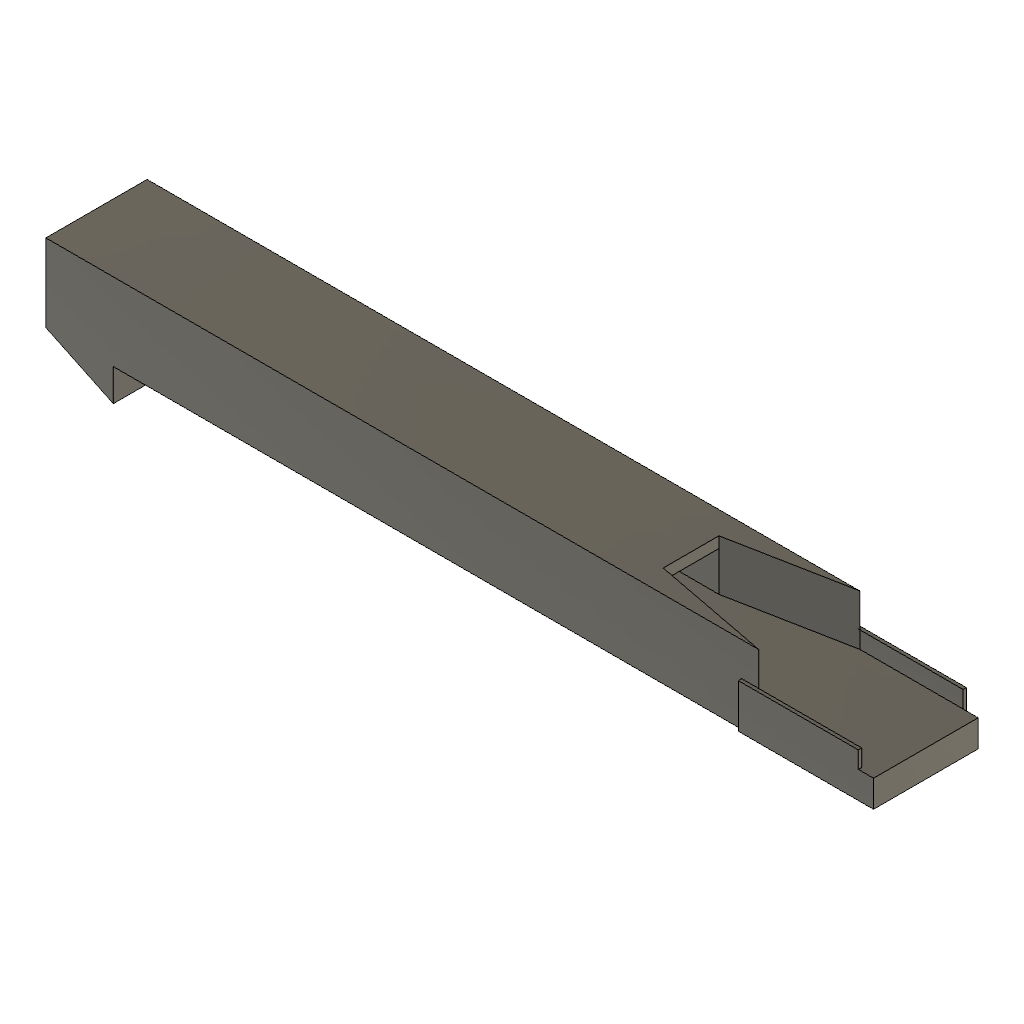
Lego ramp center (Autodesk Fusion 360 design; units mm, degrees)
Autodesk Fusion 360 part; units mm, degrees
sketch "Sketch1" plane through (0, 0, 0) normal (0, 0, 1) x (1, 0, 0)
  line L0 (-79, 15) -> (79, 15)
  line L1 (79, 15) -> (79, -15)
  line L2 (79, -15) -> (-79, -15)
  line L3 (-79, -15) -> (-79, 15)
  line L4 (-79, 15) -> (79, -15) construction
  line L5 (79, 15) -> (-79, -15) construction
  line L6 (79, 8.25) -> (-79, 8.25)
  line L7 (-79, 8.25) -> (-79, -8.25)
  line L8 (-79, -8.25) -> (79, -8.25)
  line L9 (79, -8.25) -> (79, 8.25)
  line L10 (79, 8.25) -> (-79, -8.25) construction
  line L11 (-79, 8.25) -> (79, -8.25) construction
  dimension "d1" = 158
  dimension "d2" = 30
  dimension "d3" = 16.5
  constraint horizontal L0
  constraint perpendicular L0 L1
  constraint parallel L0 L2
  constraint parallel L1 L3
  constraint coincident L4 origin
  constraint coincident L5 origin
  constraint horizontal L6
  constraint perpendicular L6 L7
  constraint parallel L6 L8
  constraint parallel L7 L9
  constraint coincident L10 origin
  constraint coincident L11 origin
  constraint coincident L3 L7.end
  measures "d1" distance of L1.end L2.end
  measures "d2" distance of L0.end L1.end
  measures "d3" distance of L6.end L7.end
extrude "Extrude1" add sketch "Sketch1" against normal blind 5 makes body 1
sketch "Sketch2" plane through (0, 0, 0) normal (0, 0, 1) x (-1, 0, 0)
  line L0 (-79, 15) -> (-79, -15)
  line L1 (-79, -15) -> (79, -15)
  line L2 (79, -15) -> (79, 15)
  line L3 (79, 15) -> (-79, 15)
  line L4 (-79, -8.25) -> (79, -8.25)
  line L5 (79, -8.25) -> (79, 8.25)
  line L6 (79, 8.25) -> (-79, 8.25)
  line L7 (-79, 8.25) -> (-79, -8.25)
  line L8 (-79, -8.25) -> (79, 8.25) construction
  line L9 (79, -8.25) -> (-79, 8.25) construction
  point P0 (-79, -8.25)
  constraint horizontal L4
  constraint perpendicular L4 L5
  constraint parallel L4 L6
  constraint parallel L5 L7
  constraint coincident L8 origin
  constraint coincident L9 origin
  constraint coincident P0 L4.start
extrude "Extrude10" add sketch "Sketch2" along normal blind 15 contours L0 L2 L3 L6 | L0 L1 L2 L4 bodies 1
sketch "Sketch3" plane through (0, 0, 0) normal (0, 0, 1) x (-1, 0, 0)
  line L0 (-79, 8.25) -> (-79, -8.25)
  line L1 (79, -8.25) -> (79, 8.25)
  line L2 (-67, -8.25) -> (-50, -8.25)
  line L3 (-50, -8.25) -> (-50, 8.25)
  line L4 (-50, 8.25) -> (-67, 8.25)
  line L5 (-67, 8.25) -> (-67, -8.25)
  line L6 (-67, -8.25) -> (-50, 8.25) construction
  line L7 (-50, -8.25) -> (-67, 8.25) construction
  line L8 (-18, -8.25) -> (7, -8.25)
  line L9 (7, -8.25) -> (7, 8.25)
  line L10 (7, 8.25) -> (-18, 8.25)
  line L11 (-18, 8.25) -> (-18, -8.25)
  line L12 (-18, -8.25) -> (7, 8.25) construction
  line L13 (7, -8.25) -> (-18, 8.25) construction
  line L14 (32, -8.25) -> (65, -8.25)
  line L15 (65, -8.25) -> (65, 8.25)
  line L16 (65, 8.25) -> (32, 8.25)
  line L17 (32, 8.25) -> (32, -8.25)
  line L18 (32, -8.25) -> (65, 8.25) construction
  line L19 (65, -8.25) -> (32, 8.25) construction
  line L20 (-79, -8.25) -> (79, -8.25)
  line L21 (79, 8.25) -> (-79, 8.25)
  point P0 (-58.5, 0)
  point P1 (-5.5, 0)
  point P2 (48.5, 0)
  dimension "d60" = 17
  dimension "d61" = 16.5
  dimension "d64" = 25
  dimension "d65" = 16.5
  dimension "d67" = 33
  dimension "d68" = 16.5
  dimension "d94" = 25
  dimension "d95" = 32
  dimension "d128" = 12
  constraint horizontal L2
  constraint perpendicular L2 L3
  constraint parallel L2 L4
  constraint parallel L3 L5
  constraint coincident L6 P0
  constraint coincident L7 P0
  constraint horizontal L8
  constraint perpendicular L8 L9
  constraint parallel L8 L10
  constraint parallel L9 L11
  constraint coincident L12 P1
  constraint coincident L13 P1
  constraint horizontal L14
  constraint perpendicular L14 L15
  constraint parallel L14 L16
  constraint parallel L15 L17
  constraint coincident L18 P2
  constraint coincident L19 P2
  measures "d60" distance of L3.end L4.end
  measures "d61" distance of L2.end L3.end
  measures "d64" distance of L9.end L10.end
  measures "d65" distance of L8.end L9.end
  measures "d67" distance of L15.end L16.end
  measures "d68" distance of L14.end L15.end
  measures "d94" distance of L9 L17
  measures "d95" distance of L3 L11
  measures "d128" distance of L0 L5
sketch "Sketch5" plane through (79, 0, 0) normal (1, 0, 0) x (0, 1, 0)
  line L0 (-15, 15) -> (-15, -5)
  line L1 (-15, -5) -> (15, -5)
  line L2 (8.25, 0) -> (8.25, 15)
  line L3 (-8.25, 10) -> (8.25, 10)
  line L4 (-1.0004, 11.75) -> (-7, 11.75)
  line L5 (-7, 11.75) -> (-7, 9.9815)
  line L6 (-1.0004, 9.9102) -> (-1.0004, 11.75)
  line L7 (-1.0004, 11.75) -> (-7, 9.9815) construction
  line L8 (-7, 11.75) -> (-1.0004, 9.9102) construction
  line L9 (7, 11.75) -> (1, 11.75)
  line L10 (1, 11.75) -> (1, 10)
  line L11 (1, 10) -> (7, 10)
  line L12 (7, 10) -> (7, 11.75)
  line L13 (7, 11.75) -> (1, 10) construction
  line L14 (1, 11.75) -> (7, 10) construction
  line L15 (1, 10.5) -> (-1.0004, 10.5)
  line L16 (7, 10.25) -> (8.25, 10.25)
  line L17 (-7, 10.25) -> (-8.25, 10.25)
  line L18 (8.25, 0) -> (-8.25, 0)
  line L19 (15, -5) -> (15, 15)
  line L20 (-8.25, 0) -> (-8.25, 15)
  line L21 (-8.25, 15) -> (-15, 15)
  line L22 (15, 15) -> (8.25, 15)
  line L23 (8.25, 15) -> (8.25, 0)
  line L24 (-8.25, 15) -> (8.25, 15)
  point P0 (-4.0595, 10.8483)
  point P1 (4, 10.875)
  dimension "d36" = 6
  dimension "d45" = 1.75
  dimension "d48" = 6
  dimension "d49" = 1.75
  dimension "d54" = 1.75
  dimension "d55" = 0.5
  dimension "d56" = 0.25
  dimension "d57" = 0.25
  constraint coincident L2.start L18.start
  constraint horizontal L4
  constraint perpendicular L4 L5
  constraint parallel L5 L6
  constraint coincident L7 P0
  constraint coincident L8 P0
  constraint horizontal L9
  constraint perpendicular L9 L10
  constraint parallel L9 L11
  constraint parallel L10 L12
  constraint coincident L13 P1
  constraint coincident L14 P1
  constraint coincident L10 L15.start
  constraint coincident L6 L15.end
  constraint perpendicular L6 L15
  constraint coincident L12 L16.start
  constraint coincident L5 L17.start
  constraint coincident L20.end L21.start
  constraint coincident L2.end L22.end
  measures "d36" distance of L5.end L6.start
  measures "d45" distance of L3 L4
  measures "d48" distance of L10.end L11.end
  measures "d49" distance of L9.end L10.end
  measures "d54" distance of L3 L9
  measures "d55" distance of L3 L15
  measures "d56" distance of L3 L17
  measures "d57" distance of L3 L16
extrude "Extrude12" cut sketch "Sketch3" against normal blind 25 contours L2 L3 L4 L5 L20 L21 | L8 L9 L10 L11 L20 L21 | L14 L15 L16 L17 L20 L21 bodies 1
extrude "Extrude13" add sketch "Sketch5" against normal blind 149 contours L2 L4 L5 L6 L9 L10 L12 L15 L16 L17 L20 L23 L24 bodies 1
sketch "Sketch7" plane through (79, 0, 0) normal (1, 0, 0) x (0, 1, 0)
  line L0 (8.25, 10.25) -> (8.25, 0)
  line L1 (8.25, 0) -> (-8.25, 0)
  line L2 (-8.25, 0) -> (-8.25, 10.25)
  line L3 (-8.25, 10.25) -> (-7, 10.25)
  line L4 (-7, 10.25) -> (-7, 11.75)
  line L5 (-7, 11.75) -> (-1.0004, 11.75)
  line L6 (-1.0004, 11.75) -> (-1.0004, 10.5)
  line L7 (-1.0004, 10.5) -> (1, 10.5)
  line L8 (1, 10.5) -> (1, 11.75)
  line L9 (1, 11.75) -> (7, 11.75)
  line L10 (7, 11.75) -> (7, 10.25)
  line L11 (7, 10.25) -> (8.25, 10.25)
  line L12 (15, 15) -> (-15, 15)
  line L13 (-15, 15) -> (-15, -5)
  line L14 (-15, -5) -> (15, -5)
  line L15 (15, -5) -> (15, 15)
  line L16 (0, 0) -> (0, -2.5)
  line L17 (25, 0) -> (-25, 0)
  line L18 (-25, 0) -> (-25, -5)
  line L19 (-25, -5) -> (25, -5)
  line L20 (25, -5) -> (25, 0)
  line L21 (25, 0) -> (-25, -5) construction
  line L22 (-25, 0) -> (25, -5) construction
  point P0 (0, -3)
  point P1 (0, -2.5)
  dimension "d84" = 2.5
  dimension "d85" = 50
  constraint coincident L16.start origin
  constraint perpendicular L1 L16
  constraint horizontal L17
  constraint perpendicular L17 L18
  constraint parallel L17 L19
  constraint parallel L18 L20
  constraint coincident L21 P1
  constraint coincident L22 P1
  constraint coincident P1 L16.end
  measures "d84" distance of L16.start P1
  measures "d85" distance of L18.end L19.end
extrude "Extrude14" add sketch "Sketch7" along normal blind 35 contours L1 L13 L14 L15 L17 L19 | L15 L17 L19 L20 | L13 L17 L18 L19 bodies 1
sketch "Sketch8" plane through (0, 0, 0) normal (0, 0, 1) x (-1, 0, 0)
  line L0 (-67, -8.25) -> (-67, 8.25)
  line L1 (-67, 8.25) -> (-79, 8.25)
  line L2 (-79, 8.25) -> (-79, 15)
  line L3 (-79, 15) -> (-79, 25)
  line L4 (-79, 25) -> (-114, 25)
  line L5 (-114, 25) -> (-114, -25)
  line L6 (-114, -25) -> (-79, -25)
  line L7 (-79, -25) -> (-79, -15)
  line L8 (-79, -15) -> (-79, -8.25)
  line L9 (-79, -8.25) -> (-67, -8.25)
  line L10 (-79, 8.25) -> (-114, 8.25)
  line L11 (-79, 15) -> (-114, 15)
  line L12 (-79, -8.25) -> (-114, -8.25)
  line L13 (-79, -15) -> (-114, -15)
  line L14 (-79, -8.25) -> (-114, -15)
  line L15 (-79, 8.25) -> (-114, 15)
  constraint coincident L1.end L2.start
  constraint coincident L5 L10.end
  constraint perpendicular L5 L10
  constraint coincident L2.end L3.start
  constraint coincident L5 L11.end
  constraint perpendicular L5 L11
  constraint coincident L8.end L9.start
  constraint coincident L5 L12.end
  constraint perpendicular L5 L12
  constraint coincident L7.end L8.start
  constraint coincident L5 L13.end
  constraint perpendicular L5 L13
extrude "Extrude15" add sketch "Sketch8" along normal blind 15 contours L8 L13 L14 | L2 L11 L15 bodies 1
extrude "Extrude16" cut sketch "Sketch8" against normal blind 10 contours L5 L6 L7 L13 | L3 L4 L5 L11 bodies 1
extrude "Extrude17" cut 1 faces at (-23.6667, 2.75, 0) along direction (0, 0, -1) blind 3 on bodies 1 bodies 1
extrude "Extrude18" cut 1 faces at (-70, -0.3335, 13.9167) along direction (1, 0, 0) blind 10 on bodies 1 bodies 1
sketch "Sketch11" plane through (-60, 0, 0) normal (-1, 0, 0) x (0, -1, 0)
  line L0 (8.25, 15) -> (-8.25, 15)
  line L1 (-8.25, 10.25) -> (-7, 10.25)
  line L2 (-7, 10.25) -> (-7, 11.75)
  line L3 (-7, 11.75) -> (-1, 11.75)
  line L4 (-1, 11.75) -> (-1, 10.5)
  line L5 (-1, 10.5) -> (1.0004, 10.5)
  line L6 (1.0004, 10.5) -> (1.0004, 11.75)
  line L7 (1.0004, 11.75) -> (7, 11.75)
  line L8 (7, 11.75) -> (7, 10.25)
  line L9 (7, 10.25) -> (8.25, 10.25)
  line L10 (8.25, 10.25) -> (8.25, 15)
  line L11 (-8.25, 15) -> (-8.25, 10.25)
extrude "Extrude19" add sketch "Sketch11" against normal blind 2 bodies 1
extrude "Extrude20" add 1 faces at (-60, -0.3335, 13.9167) along direction (-1, 0, 0) blind 10 on bodies 1 bodies 1
extrude "Extrude21" add 1 faces at (114, -5, -1.6667) along direction (1, 0, 0) blind 35 on bodies 1 bodies 1
sketch "Sketch13" plane through (0, -15, 0) normal (0, -1, 0) x (1, 0, 0)
  line L0 (-79, -5) -> (149, -5)
  line L1 (149, -5) -> (149, 0)
  line L2 (149, 0) -> (114, 0)
  line L3 (114, 0) -> (114, 15)
  line L4 (114, 15) -> (-79, 15)
  line L5 (114, 0) -> (149, 0)
  line L6 (149, 0) -> (149, -5)
  line L7 (149, -5) -> (114, -5)
  line L8 (114, -5) -> (114, 0)
  line L9 (114, 0) -> (144.5, 0)
  line L10 (144.5, 0) -> (144.5, 5)
  line L11 (144.5, 5) -> (114, 5)
  line L12 (114, 5) -> (114, 0)
  line L13 (-79, 15) -> (-79, -5)
  dimension "d105" = 5
  constraint horizontal L5
  constraint vertical L6
  constraint horizontal L7
  constraint vertical L8
  constraint coincident L0.end L1.start
  constraint coincident L2.end L3.start
  constraint horizontal L9
  constraint vertical L10
  constraint horizontal L11
  constraint vertical L12
  measures "d105" distance of L2.end L11.end
sketch "Sketch14" plane through (0, 15, 0) normal (0, 1, 0) x (-1, 0, 0)
  line L0 (79, 15) -> (-114, 15)
  line L1 (-114, 15) -> (-114, 0)
  line L2 (-114, 0) -> (-149, 0)
  line L3 (-149, 0) -> (-149, -5)
  line L4 (-149, -5) -> (79, -5)
  line L5 (-114, -5) -> (-144.5, -5)
  line L6 (-144.5, -5) -> (-144.5, 5)
  line L7 (-144.5, 5) -> (-114, 5)
  line L8 (-114, 5) -> (-114, -5)
  line L9 (79, -5) -> (79, 15)
  point P0 (-114, -5)
  point P1 (-144.5, 5)
  constraint horizontal L5
  constraint vertical L6
  constraint horizontal L7
  constraint vertical L8
  constraint coincident P1 L6.end
  constraint coincident P0 L5.start
extrude "Extrude22" add sketch "Sketch14" along normal blind 1 separate body contours L1 L2 L6 L7 L8 | L2 L4 L5 L6 L8 makes body 2
extrude "Extrude23" add sketch "Sketch13" along normal blind 1 separate body contours L0 L1 L2 L5 L6 L7 L8 L9 | L2 L3 L5 L9 L10 L11 L12 makes body 3
sketch "Sketch15" plane through (79, 0, 0) normal (1, 0, 0) x (0, 1, 0)
  line L0 (8.25, 10.25) -> (8.25, 15)
  line L1 (8.25, 15) -> (-8.25, 15)
  line L2 (-8.25, 15) -> (-8.25, 10.25)
  line L3 (-8.25, 10.25) -> (-7, 10.25)
  line L4 (-7, 10.25) -> (-7, 11.75)
  line L5 (-7, 11.75) -> (-1.0004, 11.75)
  line L6 (-1.0004, 11.75) -> (-1.0004, 10.5)
  line L7 (-1.0004, 10.5) -> (1, 10.5)
  line L8 (1, 10.5) -> (1, 11.75)
  line L9 (1, 11.75) -> (7, 11.75)
  line L10 (7, 11.75) -> (7, 10.25)
  line L11 (7, 10.25) -> (8.25, 10.25)
  line L12 (8.25, 10.25) -> (-8.25, 10.25)
  line L13 (-8.25, 10.25) -> (-8.25, 12.75)
  line L14 (-8.25, 12.75) -> (8.25, 12.75)
  line L15 (8.25, 12.75) -> (8.25, 10.25)
  dimension "d110" = 2.5
  constraint horizontal L12
  constraint vertical L13
  constraint horizontal L14
  constraint vertical L15
  constraint coincident L0.start L11.end
  measures "d110" distance of L0.start L14.end
extrude "Extrude24" cut sketch "Sketch15" against normal up to surface (158 mm away) contours L0 L2 L3 L4 L5 L6 L7 L8 L9 L10 L11 L12 L13 L14 L15 bodies 1
extrude "Extrude25" add 1 faces at (121.6667, -2.75, -5) along direction (0, 0, -1) blind 3 on bodies 1 bodies 1 2 3
extrude "Extrude26" cut 1 faces at (39.3333, -2.75, 0) along direction (0, 0, -1) blind 4 on bodies 1 bodies 1
extrude "Extrude27" cut 1 faces at (-23.6667, 2.75, -3) along direction (0, 0, -1) blind 3 on bodies 1 bodies 1
extrude "Extrude29" cut 1 faces at (-65, 2.75, -5.3333) along direction (-1, 0, 0) blind 3 on bodies 1 bodies 1
extrude "Extrude30" add 2 faces at (137.3333, -15.3333, -5) (134.3333, 15.3333, -5) along direction (0, 0, -1) up to surface end surface through (114, -15, -8) normal (0, 0, -1) offset 0 on bodies 1 bodies 1
extrude "Extrude31" add 2 faces at (114, 15.6667, -1) (114, -15.6667, -1) along direction (-1, 0, 0) blind 5 on bodies 1 bodies 1
sketch "Sketch18" plane through (-79, 0, 0) normal (-1, 0, 0) x (0, -1, 0)
  line L0 (8.25, 0) -> (-8.25, 0)
  line L1 (-8.25, 0) -> (-8.25, 15)
  line L2 (-8.25, 15) -> (-15, 15)
  line L3 (-15, 15) -> (-15, -8)
  line L4 (-15, -8) -> (15, -8)
  line L5 (15, -8) -> (15, 15)
  line L6 (15, 15) -> (8.25, 15)
  line L7 (8.25, 15) -> (8.25, 0)
  line L8 (-8.25, 15) -> (8.25, 15)
  line L9 (8.25, 15) -> (8.25, 0)
  line L10 (8.25, 0) -> (-8.25, 0)
  line L11 (-8.25, 0) -> (-8.25, 15)
  constraint horizontal L8
  constraint vertical L9
  constraint horizontal L10
  constraint vertical L11
  constraint coincident L0.start L7.end
  constraint coincident L1.end L2.start
extrude "Extrude33" add sketch "Sketch18" against normal blind 9 contours L0 L1 L7 L8 L9 L10 L11 bodies 1
extrude "Extrude34" add 1 faces at (-70, -2.75, 8.5) along direction (1, 0, 0) up to surface (2 mm away) on bodies 1 bodies 1
extrude "Extrude35" add 1 faces at (-19, -2.75, 12.75) along direction (0, 0, -1) blind 1 on bodies 1 bodies 1
extrude "Extrude36" add 1 faces at (-7, 2.75, -6.6667) along direction (1, 0, 0) blind 2.5 on bodies 1 bodies 1
extrude "Extrude37" add 1 faces at (-79, -5, -0.3333) along direction (-1, 0, 0) blind 18 on bodies 1 bodies 1
sketch "Sketch20" plane through (0, 15, 0) normal (0, 1, 0) x (-1, 0, 0)
  line L0 (-109, 5) -> (-109, -8)
  line L1 (-109, -8) -> (97, -8)
  line L2 (97, -8) -> (97, 15)
  line L3 (97, 15) -> (-114, 15)
  line L4 (-114, 15) -> (-114, 5)
  line L5 (-114, 5) -> (-109, 5)
  line L6 (97, -8) -> (77, -8)
  line L7 (97, -8) -> (72.8755, -19.5068)
  line L8 (97, -8) -> (123.7283, -8) construction
  line L9 (77, -8) -> (77, -17.5395)
  dimension "d143" = 20
  dimension "d144" = 154.5
  constraint coincident L1.end L2.start
  constraint perpendicular L2 L6
  constraint horizontal L8
  constraint coincident L7 L9.end
  constraint perpendicular L6 L9
  measures "d143" distance of L1.end L6.end
  measures "d144" angle of L7 L8
extrude "Extrude38" add sketch "Sketch20" against normal blind 30 contours L1 L6 L7 L9 bodies 1
sketch "Sketch21" plane through (-21.0865, 0, -44.2089) normal (-0.430511, 0, -0.902585) x (0, -1, 0)
  line L0 (-15, 84.1067) -> (-15, 61.9481)
  line L1 (-15, 61.9481) -> (15, 61.9481)
  line L2 (15, 61.9481) -> (15, 84.1067)
  line L3 (15, 84.1067) -> (-15, 84.1067)
  circle A0 centre (7.5, 73.0274) radius 1.875
  circle A1 centre (-7.5, 73.0274) radius 1.875
  dimension "d147" = 3.75
  dimension "d148" = 3.75
  dimension "d151" = 15
  dimension "d152" = 7.5
  dimension "d154" = 7.5
  dimension "d155" = 11.0793
  measures "d147" diameter of A0
  measures "d148" diameter of A1
  measures "d151" distance of A0.centre A1.centre
  measures "d152" distance of L2 A0.centre
  measures "d154" distance of L0 A1.centre
  measures "d155" distance of L3 A0.centre
extrude "Extrude39" cut sketch "Sketch21" against normal blind 8 contours A0 | A1 bodies 1
